Autodesk Fusion 360 part; units mm, degrees
(part 7 of 7)
  spline S13 degree 5 poles (5.565295, 1.802773) (5.560708, 1.804624) (5.551532, 1.808309) (5.537769, 1.813783) (5.519419, 1.820978) (5.496482, 1.829795) (5.473545, 1.838437) (5.45061, 1.846902) (5.427676, 1.855191) (5.404745, 1.863302) (5.381818, 1.871235) (5.358896, 1.878989) (5.335981, 1.886564) (5.313075, 1.89396) (5.290178, 1.901175) (5.267291, 1.908209) (5.244417, 1.915062) (5.221555, 1.921732) (5.198708, 1.92822) (5.175876, 1.934524) (5.15306, 1.940643) (5.130262, 1.946578) (5.107483, 1.952327) (5.084724, 1.957889) (5.061988, 1.963264) (5.039275, 1.968451) (5.016586, 1.973449) (4.993922, 1.978257) (4.971286, 1.982875) (4.948679, 1.987302) (4.926101, 1.991535) (4.903555, 1.995575) (4.881043, 1.999419) (4.858565, 2.003067) (4.836123, 2.006518) (4.813718, 2.009771) (4.791353, 2.012826) (4.769027, 2.015681) (4.746744, 2.018335) (4.724504, 2.020787) (4.702311, 2.023032) (4.680167, 2.025068) (4.658072, 2.026893) (4.636031, 2.028505) (4.614043, 2.029904) (4.592109, 2.031091) (4.570231, 2.032066) (4.54841, 2.03283) (4.526649, 2.033379) (4.504951, 2.033706) (4.483322, 2.033801) (4.461766, 2.033654) (4.440287, 2.033258) (4.418889, 2.032611) (4.397569, 2.031719) (4.376326, 2.030595) (4.355156, 2.02925) (4.33406, 2.027687) (4.313044, 2.025897) (4.292122, 2.023846) (4.271312, 2.021487) (4.250633, 2.018775) (4.230096, 2.015683) (4.209703, 2.012214) (4.189437, 2.008421) (4.169275, 2.004383) (4.149196, 2.000161) (4.129203, 1.995765) (4.10933, 1.991118) (4.089661, 1.98601) (4.070306, 1.980155) (4.055163, 1.974642) (4.044036, 1.969938) (4.036727, 1.966536) (4.033099, 1.964769) knots -1 -1 -1 -1 -1 -1 -0.98571429 -0.97142857 -0.95714286 -0.94285714 -0.92857143 -0.91428571 -0.9 -0.88571429 -0.87142857 -0.85714286 -0.84285714 -0.82857143 -0.81428571 -0.8 -0.78571429 -0.77142857 -0.75714286 -0.74285714 -0.72857143 -0.71428571 -0.7 -0.68571429 -0.67142857 -0.65714286 -0.64285714 -0.62857143 -0.61428571 -0.6 -0.58571429 -0.57142857 -0.55714286 -0.54285714 -0.52857143 -0.51428571 -0.5 -0.48571429 -0.47142857 -0.45714286 -0.44285714 -0.42857143 -0.41428571 -0.4 -0.38571429 -0.37142857 -0.35714286 -0.34285714 -0.32857143 -0.31428571 -0.3 -0.28571429 -0.27142857 -0.25714286 -0.24285714 -0.22857143 -0.21428571 -0.2 -0.18571429 -0.17142857 -0.15714286 -0.14285714 -0.12857143 -0.11428571 -0.1 -0.08571429 -0.07142857 -0.05714286 -0.04285714 -0.02857143 -0.01428571 0 0 0 0 0 0
  line L13 (4.033099, 1.964769) -> (3.513907, 1.711839)
  arc A14 (3.513907, 1.711839) -> (3.016873, 2.485239) centre (0, 0) ccw
  line L14 (3.016873, 2.485239) -> (3.462626, 2.852441)
  spline S14 degree 5 poles (3.462626, 2.852441) (3.465741, 2.855007) (3.471872, 2.860243) (3.480773, 2.86841) (3.492078, 2.879894) (3.505445, 2.895068) (3.518263, 2.910838) (3.530745, 2.926984) (3.543049, 2.943345) (3.55523, 2.959855) (3.567279, 2.976518) (3.579148, 2.993377) (3.590775, 3.010485) (3.602119, 3.027882) (3.613176, 3.045566) (3.623967, 3.063516) (3.634524, 3.081695) (3.644883, 3.100068) (3.655067, 3.118608) (3.665085, 3.137306) (3.674933, 3.156163) (3.684601, 3.175186) (3.694079, 3.194382) (3.703361, 3.213755) (3.71245, 3.233302) (3.721348, 3.253016) (3.730064, 3.272889) (3.738605, 3.292912) (3.746975, 3.313078) (3.755176, 3.333384) (3.763208, 3.353828) (3.77107, 3.37441) (3.77876, 3.39513) (3.786278, 3.415985) (3.793625, 3.436975) (3.800802, 3.458095) (3.807811, 3.479343) (3.814654, 3.500715) (3.821331, 3.522209) (3.827843, 3.543823) (3.834191, 3.565554) (3.840375, 3.587402) (3.846394, 3.609364) (3.852249, 3.631439) (3.857941, 3.653626) (3.863469, 3.675922) (3.868834, 3.698325) (3.874036, 3.720834) (3.879077, 3.743447) (3.883956, 3.766161) (3.888673, 3.788977) (3.893229, 3.811892) (3.897624, 3.834904) (3.901857, 3.858012) (3.90593, 3.881216) (3.909841, 3.904512) (3.913592, 3.9279) (3.917182, 3.951377) (3.920611, 3.974944) (3.92388, 3.998598) (3.926989, 4.022338) (3.929938, 4.046163) (3.932726, 4.070072) (3.935355, 4.094063) (3.937823, 4.118135) (3.940131, 4.142285) (3.942279, 4.166514) (3.944266, 4.190818) (3.946094, 4.215197) (3.947761, 4.239651) (3.949269, 4.264179) (3.950348, 4.283859) (3.951085, 4.298653) (3.951545, 4.30853) (3.951767, 4.313472) knots 0 0 0 0 0 0 0.01428571 0.02857143 0.04285714 0.05714286 0.07142857 0.08571429 0.1 0.11428571 0.12857143 0.14285714 0.15714286 0.17142857 0.18571429 0.2 0.21428571 0.22857143 0.24285714 0.25714286 0.27142857 0.28571429 0.3 0.31428571 0.32857143 0.34285714 0.35714286 0.37142857 0.38571429 0.4 0.41428571 0.42857143 0.44285714 0.45714286 0.47142857 0.48571429 0.5 0.51428571 0.52857143 0.54285714 0.55714286 0.57142857 0.58571429 0.6 0.61428571 0.62857143 0.64285714 0.65714286 0.67142857 0.68571429 0.7 0.71428571 0.72857143 0.74285714 0.75714286 0.77142857 0.78571429 0.8 0.81428571 0.82857143 0.84285714 0.85714286 0.87142857 0.88571429 0.9 0.91428571 0.92857143 0.94285714 0.95714286 0.97142857 0.98571429 1 1 1 1 1 1
  arc A15 (3.951767, 4.313472) -> (3.707172, 4.525415) centre (0, 0) ccw
  spline S15 degree 5 poles (3.707172, 4.525415) (3.702312, 4.524492) (3.692601, 4.522631) (3.678063, 4.519796) (3.658736, 4.515927) (3.634673, 4.510944) (3.610705, 4.505813) (3.586834, 4.500535) (3.56306, 4.495109) (3.539384, 4.489535) (3.515807, 4.483813) (3.492332, 4.477944) (3.468959, 4.471928) (3.445691, 4.465766) (3.422528, 4.459456) (3.399472, 4.453) (3.376524, 4.446398) (3.353685, 4.43965) (3.330957, 4.432755) (3.308341, 4.425714) (3.285839, 4.418527) (3.263451, 4.411194) (3.24118, 4.403715) (3.219028, 4.396091) (3.196995, 4.38832) (3.175083, 4.380404) (3.153293, 4.372342) (3.131628, 4.364134) (3.110089, 4.355781) (3.088677, 4.347282) (3.067395, 4.338637) (3.046244, 4.329847) (3.025227, 4.320909) (3.004345, 4.311826) (2.9836, 4.302596) (2.962993, 4.29322) (2.942526, 4.283698) (2.922201, 4.27403) (2.90202, 4.264215) (2.881986, 4.254254) (2.862102, 4.244144) (2.842372, 4.233885) (2.822799, 4.223475) (2.803385, 4.212914) (2.784131, 4.202204) (2.765038, 4.191344) (2.746105, 4.180336) (2.727336, 4.169181) (2.708732, 4.157878) (2.690302, 4.146423) (2.672055, 4.134809) (2.654, 4.123032) (2.636145, 4.111086) (2.618493, 4.098973) (2.60104, 4.086696) (2.583777, 4.074265) (2.566695, 4.061688) (2.549793, 4.048969) (2.533081, 4.036101) (2.516589, 4.023064) (2.500358, 4.009828) (2.484428, 3.996367) (2.468823, 3.982663) (2.453543, 3.968719) (2.438545, 3.954572) (2.423766, 3.940274) (2.409157, 3.925867) (2.394714, 3.91136) (2.380509, 3.896707) (2.366724, 3.881776) (2.353607, 3.866386) (2.343848, 3.853561) (2.337031, 3.843588) (2.332721, 3.836775) (2.330624, 3.833326) knots -1 -1 -1 -1 -1 -1 -0.98571429 -0.97142857 -0.95714286 -0.94285714 -0.92857143 -0.91428571 -0.9 -0.88571429 -0.87142857 -0.85714286 -0.84285714 -0.82857143 -0.81428571 -0.8 -0.78571429 -0.77142857 -0.75714286 -0.74285714 -0.72857143 -0.71428571 -0.7 -0.68571429 -0.67142857 -0.65714286 -0.64285714 -0.62857143 -0.61428571 -0.6 -0.58571429 -0.57142857 -0.55714286 -0.54285714 -0.52857143 -0.51428571 -0.5 -0.48571429 -0.47142857 -0.45714286 -0.44285714 -0.42857143 -0.41428571 -0.4 -0.38571429 -0.37142857 -0.35714286 -0.34285714 -0.32857143 -0.31428571 -0.3 -0.28571429 -0.27142857 -0.25714286 -0.24285714 -0.22857143 -0.21428571 -0.2 -0.18571429 -0.17142857 -0.15714286 -0.14285714 -0.12857143 -0.11428571 -0.1 -0.08571429 -0.07142857 -0.05714286 -0.04285714 -0.02857143 -0.01428571 0 0 0 0 0 0
  line L15 (2.330624, 3.833326) -> (2.030597, 3.339852)
  arc A16 (2.030597, 3.339852) -> (1.194334, 3.721761) centre (0, 0) ccw
  line L16 (1.194334, 3.721761) -> (1.370801, 4.271663)
  spline S16 degree 5 poles (1.370801, 4.271663) (1.372034, 4.275506) (1.374361, 4.283225) (1.377433, 4.294908) (1.380735, 4.310681) (1.383776, 4.330673) (1.386033, 4.350869) (1.387804, 4.371201) (1.38931, 4.391616) (1.390631, 4.412091) (1.391759, 4.432623) (1.392629, 4.453222) (1.393161, 4.473901) (1.393299, 4.494669) (1.39304, 4.515524) (1.392413, 4.536458) (1.391466, 4.557459) (1.390247, 4.578516) (1.388792, 4.599619) (1.38711, 4.620765) (1.385199, 4.641952) (1.383048, 4.663182) (1.380644, 4.684455) (1.377979, 4.705771) (1.375056, 4.727128) (1.371884, 4.748524) (1.368472, 4.769954) (1.364832, 4.791416) (1.360971, 4.812906) (1.356892, 4.834422) (1.352596, 4.855964) (1.348082, 4.877529) (1.34335, 4.899117) (1.338399, 4.920726) (1.333232, 4.942356) (1.327851, 4.964004) (1.32226, 4.985668) (1.316461, 5.007347) (1.310458, 5.029038) (1.304251, 5.050742) (1.297843, 5.072455) (1.291233, 5.094178) (1.284423, 5.115908) (1.277414, 5.137644) (1.270207, 5.159386) (1.262803, 5.181131) (1.255205, 5.202878) (1.247412, 5.224627) (1.239427, 5.246375) (1.231251, 5.268122) (1.222885, 5.289866) (1.214329, 5.311606) (1.205584, 5.333341) (1.196652, 5.35507) (1.187534, 5.376791) (1.178229, 5.398504) (1.16874, 5.420207) (1.159067, 5.441898) (1.149211, 5.463578) (1.139173, 5.485245) (1.128953, 5.506897) (1.118553, 5.528534) (1.107973, 5.550155) (1.097213, 5.571758) (1.086276, 5.593343) (1.075161, 5.614908) (1.063869, 5.636451) (1.052401, 5.657972) (1.040758, 5.679469) (1.02894, 5.700942) (1.016948, 5.722391) (1.007215, 5.739531) (0.999837, 5.752375) (0.994884, 5.760932) (0.992399, 5.76521) knots 0 0 0 0 0 0 0.01428571 0.02857143 0.04285714 0.05714286 0.07142857 0.08571429 0.1 0.11428571 0.12857143 0.14285714 0.15714286 0.17142857 0.18571429 0.2 0.21428571 0.22857143 0.24285714 0.25714286 0.27142857 0.28571429 0.3 0.31428571 0.32857143 0.34285714 0.35714286 0.37142857 0.38571429 0.4 0.41428571 0.42857143 0.44285714 0.45714286 0.47142857 0.48571429 0.5 0.51428571 0.52857143 0.54285714 0.55714286 0.57142857 0.58571429 0.6 0.61428571 0.62857143 0.64285714 0.65714286 0.67142857 0.68571429 0.7 0.71428571 0.72857143 0.74285714 0.75714286 0.77142857 0.78571429 0.8 0.81428571 0.82857143 0.84285714 0.85714286 0.87142857 0.88571429 0.9 0.91428571 0.92857143 0.94285714 0.95714286 0.97142857 0.98571429 1 1 1 1 1 1
  arc A17 (0.992399, 5.76521) -> (0.672048, 5.811269) centre (0, 0) ccw
  spline S17 degree 5 poles (0.672048, 5.811269) (0.668458, 5.807865) (0.661294, 5.80105) (0.650597, 5.790805) (0.63643, 5.777102) (0.618881, 5.7599) (0.601492, 5.742626) (0.584264, 5.72528) (0.567197, 5.707862) (0.550293, 5.690372) (0.533553, 5.672813) (0.516977, 5.655184) (0.500567, 5.637487) (0.484325, 5.619722) (0.46825, 5.601892) (0.452344, 5.583996) (0.436608, 5.566035) (0.421043, 5.54801) (0.405651, 5.529922) (0.390432, 5.511772) (0.375387, 5.49356) (0.360518, 5.475288) (0.345826, 5.456956) (0.331313, 5.438565) (0.316978, 5.420115) (0.302825, 5.401609) (0.288853, 5.383047) (0.275064, 5.364429) (0.26146, 5.345757) (0.248042, 5.327031) (0.234812, 5.308253) (0.221772, 5.289423) (0.208923, 5.270541) (0.196267, 5.25161) (0.183805, 5.23263) (0.171539, 5.213601) (0.159469, 5.194526) (0.147597, 5.175404) (0.135926, 5.156237) (0.124458, 5.137026) (0.113196, 5.117771) (0.102145, 5.098473) (0.091306, 5.079134) (0.080684, 5.059753) (0.070277, 5.040333) (0.060086, 5.020875) (0.05011, 5.001379) (0.040351, 4.981848) (0.030812, 4.962281) (0.021501, 4.94268) (0.012429, 4.923044) (0.003608, 4.903375) (-0.004955, 4.883674) (-0.013255, 4.86394) (-0.0213, 4.844176) (-0.029103, 4.824385) (-0.036673, 4.80457) (-0.044015, 4.784731) (-0.051117, 4.764871) (-0.057943, 4.744987) (-0.064442, 4.725078) (-0.070566, 4.705141) (-0.076284, 4.685175) (-0.0816, 4.665184) (-0.086569, 4.645175) (-0.091271, 4.625156) (-0.095772, 4.605138) (-0.100079, 4.585126) (-0.104108, 4.565119) (-0.107632, 4.545105) (-0.110346, 4.525067) (-0.111622, 4.509002) (-0.111965, 4.496927) (-0.111907, 4.488864) (-0.111807, 4.48483) knots -1 -1 -1 -1 -1 -1 -0.98571429 -0.97142857 -0.95714286 -0.94285714 -0.92857143 -0.91428571 -0.9 -0.88571429 -0.87142857 -0.85714286 -0.84285714 -0.82857143 -0.81428571 -0.8 -0.78571429 -0.77142857 -0.75714286 -0.74285714 -0.72857143 -0.71428571 -0.7 -0.68571429 -0.67142857 -0.65714286 -0.64285714 -0.62857143 -0.61428571 -0.6 -0.58571429 -0.57142857 -0.55714286 -0.54285714 -0.52857143 -0.51428571 -0.5 -0.48571429 -0.47142857 -0.45714286 -0.44285714 -0.42857143 -0.41428571 -0.4 -0.38571429 -0.37142857 -0.35714286 -0.34285714 -0.32857143 -0.31428571 -0.3 -0.28571429 -0.27142857 -0.25714286 -0.24285714 -0.22857143 -0.21428571 -0.2 -0.18571429 -0.17142857 -0.15714286 -0.14285714 -0.12857143 -0.11428571 -0.1 -0.08571429 -0.07142857 -0.05714286 -0.04285714 -0.02857143 -0.01428571 0 0 0 0 0 0
  line L17 (-0.111807, 4.48483) -> (-0.097414, 3.907486)
  arc A18 (-0.097414, 3.907486) -> (-1.007398, 3.77665) centre (0, 0) ccw
  line L18 (-1.007398, 3.77665) -> (-1.156245, 4.334663)
  spline S18 degree 5 poles (-1.156245, 4.334663) (-1.157285, 4.338562) (-1.159501, 4.346314) (-1.163232, 4.357803) (-1.168982, 4.372858) (-1.177232, 4.391319) (-1.186252, 4.40953) (-1.195754, 4.427592) (-1.205525, 4.44558) (-1.215483, 4.463519) (-1.225635, 4.481402) (-1.236039, 4.499201) (-1.246772, 4.516885) (-1.257884, 4.53443) (-1.269377, 4.551835) (-1.281222, 4.569107) (-1.293373, 4.586262) (-1.305782, 4.603317) (-1.318416, 4.620283) (-1.331263, 4.637163) (-1.344325, 4.653954) (-1.357612, 4.67065) (-1.371136, 4.687246) (-1.384902, 4.703738) (-1.398907, 4.720125) (-1.413144, 4.736409) (-1.4276, 4.752593) (-1.442265, 4.76868) (-1.457132, 4.784671) (-1.472196, 4.800566) (-1.487456, 4.816365) (-1.502913, 4.832067) (-1.518565, 4.847669) (-1.534413, 4.863172) (-1.550453, 4.878574) (-1.566684, 4.893876) (-1.5831, 4.909078) (-1.599698, 4.924181) (-1.616476, 4.939183) (-1.633431, 4.954086) (-1.650562, 4.968888) (-1.667866, 4.983588) (-1.685343, 4.998187) (-1.702991, 5.012683) (-1.720808, 5.027077) (-1.738793, 5.041368) (-1.756943, 5.055555) (-1.775257, 5.069638) (-1.793732, 5.083616) (-1.812367, 5.097491) (-1.831161, 5.11126) (-1.850113, 5.124923) (-1.86922, 5.13848) (-1.888481, 5.151931) (-1.907896, 5.165274) (-1.927462, 5.178509) (-1.947178, 5.191637) (-1.967043, 5.204655) (-1.987056, 5.217565) (-2.007214, 5.230365) (-2.027517, 5.243054) (-2.047965, 5.255634) (-2.068554, 5.268103) (-2.089285, 5.28046) (-2.110156, 5.292705) (-2.131166, 5.304837) (-2.152312, 5.316855) (-2.173595, 5.32876) (-2.195012, 5.340549) (-2.216563, 5.352225) (-2.238248, 5.363785) (-2.255702, 5.372942) (-2.268852, 5.379758) (-2.277645, 5.38428) (-2.282049, 5.386534) knots 0 0 0 0 0 0 0.01428571 0.02857143 0.04285714 0.05714286 0.07142857 0.08571429 0.1 0.11428571 0.12857143 0.14285714 0.15714286 0.17142857 0.18571429 0.2 0.21428571 0.22857143 0.24285714 0.25714286 0.27142857 0.28571429 0.3 0.31428571 0.32857143 0.34285714 0.35714286 0.37142857 0.38571429 0.4 0.41428571 0.42857143 0.44285714 0.45714286 0.47142857 0.48571429 0.5 0.51428571 0.52857143 0.54285714 0.55714286 0.57142857 0.58571429 0.6 0.61428571 0.62857143 0.64285714 0.65714286 0.67142857 0.68571429 0.7 0.71428571 0.72857143 0.74285714 0.75714286 0.77142857 0.78571429 0.8 0.81428571 0.82857143 0.84285714 0.85714286 0.87142857 0.88571429 0.9 0.91428571 0.92857143 0.94285714 0.95714286 0.97142857 0.98571429 1 1 1 1 1 1
  arc A19 (-2.282049, 5.386534) -> (-2.576447, 5.252087) centre (0, 0) ccw
  spline S19 degree 5 poles (-2.576447, 5.252087) (-2.577627, 5.247283) (-2.579968, 5.237676) (-2.583428, 5.223274) (-2.587938, 5.204087) (-2.593402, 5.180128) (-2.598691, 5.156195) (-2.603806, 5.132289) (-2.608746, 5.108409) (-2.613511, 5.084557) (-2.618101, 5.060734) (-2.622514, 5.036942) (-2.626751, 5.013183) (-2.630812, 4.989457) (-2.634695, 4.965766) (-2.6384, 4.942112) (-2.641928, 4.918495) (-2.645277, 4.894916) (-2.648446, 4.871378) (-2.651437, 4.847881) (-2.654247, 4.824427) (-2.656877, 4.801016) (-2.659325, 4.777651) (-2.661592, 4.754333) (-2.663677, 4.731063) (-2.665578, 4.707842) (-2.667296, 4.684673) (-2.668831, 4.661556) (-2.67018, 4.638493) (-2.671344, 4.615486) (-2.672322, 4.592536) (-2.673111, 4.569644) (-2.673713, 4.546814) (-2.674125, 4.524045) (-2.674347, 4.501341) (-2.674378, 4.478701) (-2.674219, 4.456128) (-2.673868, 4.433624) (-2.673324, 4.41119) (-2.672585, 4.388828) (-2.671649, 4.366541) (-2.670513, 4.344332) (-2.669175, 4.322203) (-2.667634, 4.300156) (-2.665889, 4.278193) (-2.663942, 4.256314) (-2.661794, 4.23452) (-2.659445, 4.212812) (-2.656891, 4.191194) (-2.654127, 4.169671) (-2.651143, 4.148248) (-2.64793, 4.126932) (-2.644481, 4.105729) (-2.640795, 4.08464) (-2.636878, 4.063664) (-2.632742, 4.042797) (-2.628398, 4.022034) (-2.623849, 4.001376) (-2.619086, 3.980829) (-2.614078, 3.960411) (-2.608782, 3.940149) (-2.603155, 3.920066) (-2.597172, 3.900178) (-2.590836, 3.880486) (-2.584197, 3.860967) (-2.57733, 3.841584) (-2.570294, 3.822311) (-2.563098, 3.803147) (-2.55567, 3.784138) (-2.547815, 3.765395) (-2.539265, 3.747071) (-2.531653, 3.732866) (-2.525413, 3.722523) (-2.521006, 3.715771) (-2.51874, 3.712432) knots -1 -1 -1 -1 -1 -1 -0.98571429 -0.97142857 -0.95714286 -0.94285714 -0.92857143 -0.91428571 -0.9 -0.88571429 -0.87142857 -0.85714286 -0.84285714 -0.82857143 -0.81428571 -0.8 -0.78571429 -0.77142857 -0.75714286 -0.74285714 -0.72857143 -0.71428571 -0.7 -0.68571429 -0.67142857 -0.65714286 -0.64285714 -0.62857143 -0.61428571 -0.6 -0.58571429 -0.57142857 -0.55714286 -0.54285714 -0.52857143 -0.51428571 -0.5 -0.48571429 -0.47142857 -0.45714286 -0.44285714 -0.42857143 -0.41428571 -0.4 -0.38571429 -0.37142857 -0.35714286 -0.34285714 -0.32857143 -0.31428571 -0.3 -0.28571429 -0.27142857 -0.25714286 -0.24285714 -0.22857143 -0.21428571 -0.2 -0.18571429 -0.17142857 -0.15714286 -0.14285714 -0.12857143 -0.11428571 -0.1 -0.08571429 -0.07142857 -0.05714286 -0.04285714 -0.02857143 -0.01428571 0 0 0 0 0 0
  line L19 (-2.51874, 3.712432) -> (-2.194496, 3.234521)
  arc A20 (-2.194496, 3.234521) -> (-2.889288, 2.632479) centre (0, 0) ccw
  line L20 (-2.889288, 2.632479) -> (-3.316191, 3.021437)
  spline S20 degree 5 poles (-3.316191, 3.021437) (-3.319174, 3.024155) (-3.325229, 3.029478) (-3.334579, 3.037126) (-3.347556, 3.046682) (-3.364477, 3.057753) (-3.381911, 3.068196) (-3.399669, 3.078254) (-3.417614, 3.088104) (-3.43569, 3.097811) (-3.453898, 3.107367) (-3.472274, 3.116715) (-3.490864, 3.125789) (-3.509698, 3.134542) (-3.528775, 3.14297) (-3.548078, 3.151096) (-3.567575, 3.158959) (-3.587235, 3.166597) (-3.607036, 3.17404) (-3.626969, 3.181295) (-3.647035, 3.188358) (-3.66724, 3.195221) (-3.68759, 3.201871) (-3.708086, 3.208302) (-3.728728, 3.214515) (-3.749508, 3.220518) (-3.770419, 3.226317) (-3.791454, 3.231921) (-3.812606, 3.237336) (-3.833872, 3.242564) (-3.855251, 3.247604) (-3.876743, 3.252457) (-3.898346, 3.25712) (-3.920059, 3.261594) (-3.941881, 3.265879) (-3.963807, 3.269977) (-3.985836, 3.273891) (-4.007965, 3.277622) (-4.03019, 3.281172) (-4.052511, 3.284542) (-4.074924, 3.287733) (-4.097429, 3.290745) (-4.120025, 3.293577) (-4.142709, 3.296231) (-4.165479, 3.298707) (-4.188335, 3.301006) (-4.211274, 3.303128) (-4.234294, 3.305074) (-4.257394, 3.306846) (-4.280572, 3.308442) (-4.303827, 3.309865) (-4.327156, 3.311113) (-4.35056, 3.312188) (-4.374036, 3.31309) (-4.397582, 3.313818) (-4.421198, 3.314374) (-4.444881, 3.314758) (-4.468631, 3.314971) (-4.492446, 3.315011) (-4.516325, 3.314881) (-4.540266, 3.314579) (-4.564268, 3.314107) (-4.58833, 3.313465) (-4.612451, 3.312652) (-4.636629, 3.31167) (-4.660862, 3.310517) (-4.685149, 3.309195) (-4.709489, 3.307704) (-4.73388, 3.306043) (-4.758323, 3.304214) (-4.782815, 3.302215) (-4.802449, 3.300482) (-4.817197, 3.299107) (-4.827038, 3.298156) (-4.831962, 3.297673) knots 0 0 0 0 0 0 0.01428571 0.02857143 0.04285714 0.05714286 0.07142857 0.08571429 0.1 0.11428571 0.12857143 0.14285714 0.15714286 0.17142857 0.18571429 0.2 0.21428571 0.22857143 0.24285714 0.25714286 0.27142857 0.28571429 0.3 0.31428571 0.32857143 0.34285714 0.35714286 0.37142857 0.38571429 0.4 0.41428571 0.42857143 0.44285714 0.45714286 0.47142857 0.48571429 0.5 0.51428571 0.52857143 0.54285714 0.55714286 0.57142857 0.58571429 0.6 0.61428571 0.62857143 0.64285714 0.65714286 0.67142857 0.68571429 0.7 0.71428571 0.72857143 0.74285714 0.75714286 0.77142857 0.78571429 0.8 0.81428571 0.82857143 0.84285714 0.85714286 0.87142857 0.88571429 0.9 0.91428571 0.92857143 0.94285714 0.95714286 0.97142857 0.98571429 1 1 1 1 1 1
  arc A21 (-4.831962, 3.297673) -> (-5.006938, 3.025404) centre (0, 0) ccw
  spline S21 degree 5 poles (-5.006938, 3.025404) (-5.005333, 3.020725) (-5.002109, 3.011378) (-4.997234, 2.997391) (-4.990654, 2.978812) (-4.982297, 2.955703) (-4.973808, 2.932709) (-4.965186, 2.909832) (-4.956431, 2.887072) (-4.947545, 2.864431) (-4.938526, 2.841908) (-4.929376, 2.819507) (-4.920095, 2.797229) (-4.910683, 2.775074) (-4.901142, 2.753045) (-4.891471, 2.731142) (-4.88167, 2.709367) (-4.87174, 2.687721) (-4.861681, 2.666206) (-4.851493, 2.644822) (-4.841177, 2.623572) (-4.830732, 2.602456) (-4.82016, 2.581476) (-4.80946, 2.560634) (-4.798633, 2.539931) (-4.787679, 2.519369) (-4.776598, 2.498948) (-4.765391, 2.478672) (-4.754057, 2.45854) (-4.742598, 2.438556) (-4.731012, 2.418721) (-4.719301, 2.399036) (-4.707463, 2.379505) (-4.6955, 2.360128) (-4.683412, 2.340908) (-4.671199, 2.321845) (-4.658861, 2.302942) (-4.646399, 2.2842) (-4.633812, 2.265621) (-4.621101, 2.247208) (-4.608265, 2.228966) (-4.595302, 2.210896) (-4.582212, 2.193003) (-4.568996, 2.17529) (-4.555654, 2.157756) (-4.542188, 2.140403) (-4.528598, 2.12323) (-4.514886, 2.106239) (-4.50105, 2.089433) (-4.487088, 2.072821) (-4.472996, 2.056412) (-4.458769, 2.040217) (-4.444404, 2.024244) (-4.429902, 2.008496) (-4.415266, 1.992968) (-4.400505, 1.977649) (-4.385625, 1.962531) (-4.370629, 1.947611) (-4.355514, 1.932901) (-4.340263, 1.918432) (-4.324852, 1.90425) (-4.309261, 1.890397) (-4.293475, 1.876901) (-4.277499, 1.863761) (-4.261361, 1.850929) (-4.245105, 1.838336) (-4.228766, 1.825926) (-4.212352, 1.813695) (-4.195826, 1.801719) (-4.179085, 1.7902) (-4.161985, 1.779406) (-4.147902, 1.771572) (-4.13706, 1.766244) (-4.129703, 1.762947) (-4.125991, 1.761363) knots -1 -1 -1 -1 -1 -1 -0.98571429 -0.97142857 -0.95714286 -0.94285714 -0.92857143 -0.91428571 -0.9 -0.88571429 -0.87142857 -0.85714286 -0.84285714 -0.82857143 -0.81428571 -0.8 -0.78571429 -0.77142857 -0.75714286 -0.74285714 -0.72857143 -0.71428571 -0.7 -0.68571429 -0.67142857 -0.65714286 -0.64285714 -0.62857143 -0.61428571 -0.6 -0.58571429 -0.57142857 -0.55714286 -0.54285714 -0.52857143 -0.51428571 -0.5 -0.48571429 -0.47142857 -0.45714286 -0.44285714 -0.42857143 -0.41428571 -0.4 -0.38571429 -0.37142857 -0.35714286 -0.34285714 -0.32857143 -0.31428571 -0.3 -0.28571429 -0.27142857 -0.25714286 -0.24285714 -0.22857143 -0.21428571 -0.2 -0.18571429 -0.17142857 -0.15714286 -0.14285714 -0.12857143 -0.11428571 -0.1 -0.08571429 -0.07142857 -0.05714286 -0.04285714 -0.02857143 -0.01428571 0 0 0 0 0 0
  line L21 (-4.125991, 1.761363) -> (-3.594841, 1.534618)
  circle A22 centre (0, 0) radius 1
  circle A23 centre (0, 0) radius 2.5
  dimension "d31" = 5
  constraint concentric A0 A23
  measures "d31" diameter of A23
extrude "Extrude9" [suppressed]
fillet "Fillet4" [suppressed]
fillet "Fillet5" [suppressed]
hidden bodies 1
named bodies: "Spur Gear (32 teeth)", "Spur Gear (32 teeth) (1)", "Spur Gear (11 teeth)"
